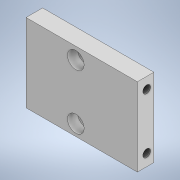
# Autodesk Inventor part: Subconjunto palanca - pieza eje 2
Saved by Autodesk Inventor 2020.2 (Build 242310000, 310)
## iProperties
Created: 2020-09-29
Part Number: Subconjunto palanca - pieza eje 2
Material: Genérico
Document SubType Name: Modeling
Designer: Salvador
Density: 1 g/cm^3
Appearance: Valor por defecto
Author: Salvador
Autodesk Inventor part; units mm, degrees
ref_plane "YZ Plane" through (0, 0, 0) normal (1, 0, 0) x (0, 1, 0)
ref_plane "XZ Plane" through (0, 0, 0) normal (0, 1, 0) x (-1, 0, 0)
ref_plane "XY Plane" through (0, 0, 0) normal (0, 0, 1) x (1, 0, 0)
sketch "Boceto1" plane through (0, 0, 0) normal (0, 0, 1) x (1, 0, 0)
  line L0 (-19.92, 0) -> (119.52, 0) projected
  line L1 (0, -14) -> (0, 84) projected
  line L2 (0, 0) -> (99.6, 0)
  line L3 (99.6, 0) -> (99.6, 70)
  line L4 (99.6, 70) -> (0, 70)
  line L5 (0, 70) -> (0, 0)
  circle A0 centre (44.5, 59.3) radius 4
  circle A1 centre (44.5, 10) radius 4
  dimension "d0" = 99.6
  dimension "d1" = 70
  dimension "d2" = 8
  dimension "d3" = 44.5
  dimension "d4" = 59.3
  dimension "d5" = 8
  dimension "d6" = 44.5
  dimension "d7" = 10
  constraints: 8 end point, 2 centre point, 2 parallel, 1 horizontal, 1 perpendicular
  measures "d0" distance of L4.end L3.end
  measures "d1" distance of L3.end L2.end
  measures "d2" diameter of A0
  measures "d3" distance from line of L1 A0.centre
  measures "d4" distance from line of L0 A0.centre
  measures "d5" diameter of A1
  measures "d6" distance from line of L1 A1.centre
  measures "d7" distance from line of L0 A1.centre
extrude "Extrusión1" add sketch "Boceto1" against normal blind 14.8 contours L1 L4 L3 L0 | A0 | A1
hole "Agujero1" at (44.5, 59.3, 0) direction (0, 0, -1) diameter 9 depth 14.8 tip angle 118 counterbore diameter 14.9 counterbore depth 9
hole "Agujero2" at (44.5, 10, 0) direction (0, 0, -1) diameter 9 depth 14.8 tip angle 118 counterbore diameter 14.9 counterbore depth 9
sketch "Boceto2" plane through (44.5, 59.3, -9) normal (0, 0, 1) x (1, 0, 0)
  circle A0 centre (0, 0) radius 4.5 projected
  point P0 (-44.5, -59.3)
  constraints: 1 coincident
hole "Agujero3" at (44.5, 59.3, -9) direction (0, 0, -1) diameter 9 depth 14.8 tip angle 118 countersink diameter 14.9 countersink angle 90
sketch "Boceto3" plane through (44.5, 10, -9) normal (0, 0, 1) x (1, 0, 0)
  circle A0 centre (0, 0) radius 4.5 projected
  point P0 (-44.5, -10)
  constraints: 1 coincident
hole "Agujero4" at (44.5, 10, -9) direction (0, 0, -1) diameter 9 depth 14.8 tip angle 118 countersink diameter 14.9 countersink angle 90
sketch "Boceto4" plane through (0, 0, 0) normal (-1, 0, 0) x (0, 0, 1)
  line L0 (0, 70) -> (0, 0) projected
  line L1 (0, 70) -> (-14.8, 70) projected
  point P0 (-8.3, 60)
  dimension "d38" = 8.3
  dimension "d46" = 10
  measures "d38" distance from line of L0 point (-8.3, 60)
  measures "d46" distance from line of L1 point (-8.3, 60)
hole "Agujero5" at (0, 60, -8.3) direction (1, 0, 0) diameter 6.917 depth 20 tip angle 118 thread size "M8x1" class "6H" standard "ISO Metric profile"
sketch "Boceto5" plane through (0, 0, 0) normal (-1, 0, 0) x (0, 0, 1)
  line L0 (0, 70) -> (0, 0) projected
  line L1 (0, 70) -> (-14.8, 70) projected
  point P0 (-8.3, 10.5)
  dimension "d47" = 8.3
  dimension "d48" = 59.5
  measures "d47" distance from line of L0 point (-8.3, 10.5)
  measures "d48" distance from line of L1 point (-8.3, 10.5)
hole "Agujero6" at (0, 10.5, -8.3) direction (1, 0, 0) diameter 6.917 depth 20 tip angle 118 thread size "M8x1" class "6H" standard "ISO Metric profile"
sketch "Boceto6" plane through (99.6, 0, 0) normal (1, 0, 0) x (0, 0, -1)
  line L0 (14.8, 70) -> (14.8, 0) projected
  line L1 (0, 70) -> (14.8, 70) projected
  point P0 (0, 0)
  point P1 (8.3, 60)
  dimension "d56" = 6.5
  dimension "d57" = 10
  measures "d56" distance from line of L0 point (8.3, 60)
  measures "d57" distance from line of L1 point (8.3, 60)
hole "Agujero7" at (99.6, 60, -8.3) direction (-1, 0, 0) diameter 6.917 depth 20 tip angle 118 thread size "M8x1" class "6H" standard "ISO Metric profile"
sketch "Boceto7" plane through (99.6, 0, 0) normal (1, 0, 0) x (0, 0, -1)
  line L0 (14.8, 70) -> (14.8, 0) projected
  line L1 (0, 70) -> (14.8, 70) projected
  point P0 (0, 0)
  point P1 (8.3, 10.5)
  dimension "d65" = 6.5
  dimension "d66" = 59.5
  measures "d65" distance from line of L0 point (8.3, 10.5)
  measures "d66" distance from line of L1 point (8.3, 10.5)
hole "Agujero8" at (99.6, 10.5, -8.3) direction (-1, 0, 0) diameter 6.917 depth 20 tip angle 118 thread size "M8x1" class "6H" standard "ISO Metric profile"
equation "\"d40\" = d38"
equation "\"d59\" = d38"
equation "\"d68\" = d38"
